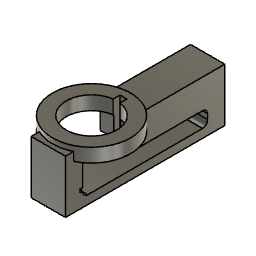
lens-mount (Autodesk Fusion 360 design; units mm, degrees)
Autodesk Fusion 360 part; units mm, degrees
sketch "スケッチ1" plane through (0, 0, 0) normal (0, 0, 1) x (1, 0, 0)
  circle A0 centre (0, 0) radius 14.75
  line L0 (-10, 10.8426) -> (-10, 57.8)
  line L1 (-10, 57.8) -> (10, 57.8)
  line L2 (10, 57.8) -> (10, 10.8426)
  line L3 (-10, -10.8426) -> (-10, -15.2)
  line L4 (10, -15.2) -> (10, -10.8426)
  line L5 (-10, -15.2) -> (10, -15.2)
  line L6 (-10, 57.8) -> (10, 57.8)
  line L7 (10, 57.8) -> (10, 67.8)
  line L8 (10, 67.8) -> (-10, 67.8)
  line L9 (-10, 67.8) -> (-10, 57.8)
  line L10 (-10, -15.2) -> (10, -15.2)
  line L11 (10, -15.2) -> (10, -25.2)
  line L12 (10, -25.2) -> (-10, -25.2)
  line L13 (-10, -25.2) -> (-10, -15.2)
  circle A1 centre (0, 0) radius 22.75
  line L14 (-2, 14.6138) -> (2, 14.6138)
  line L15 (2, 14.6138) -> (2, 18.6138)
  line L16 (2, 18.6138) -> (-2, 18.6138)
  line L17 (-2, 18.6138) -> (-2, 14.6138)
  line L18 (10, 14.9991) -> (-10, 15.0009)
  dimension "d1" = 29.5
  dimension "d2" = 73
  dimension "d3" = 20
  dimension "d4" = 15.2
  dimension "d5" = 10
  dimension "d6" = 8
  dimension "d7" = 4
  dimension "d8" = 4
  dimension "d17" = 15
  constraint coincident A0.centre A1.centre
  constraint coincident A0 L0.start
  constraint vertical L0
  constraint perpendicular L0 L1
  constraint coincident A0 L2.end
  constraint perpendicular L1 L2
  constraint coincident A0 L3.start
  constraint parallel L0 L3
  constraint coincident A0 L4.end
  constraint parallel L0 L4
  constraint perpendicular L3 L5
  constraint equal L0 L2
  constraint equal L3 L4
  constraint equal L1 L5
  constraint horizontal L6
  constraint vertical L7
  constraint horizontal L8
  constraint vertical L9
  constraint horizontal L10
  constraint vertical L11
  constraint horizontal L12
  constraint vertical L13
  constraint equal L7 L11
  constraint coincident L1.end L2.start
  constraint coincident L4.start L5.end
  constraint concentric A0 A1
  constraint horizontal L14
  constraint vertical L15
  constraint horizontal L16
  constraint vertical L17
  constraint coincident A0 L14.start
  constraint coincident A0 L14.end
  constraint coincident L2 L18.start
  constraint coincident L0 L18.end
  measures "d1" diameter of A0
  measures "d2" distance of L1 L5
  measures "d3" distance of L0.end L1.end
  measures "d4" distance of A0.centre L5
  measures "d5" distance of L1.end L7.end
  measures "d6" distance of A0 A1
  measures "d7" distance of L15.end L16.end
  measures "d8" distance of L14.end L15.end
  measures "d17" distance of A0.centre L18
extrude "押し出し1" add sketch "スケッチ1" along normal blind 8 contours A0 L2 L4 L11 A1 | A0 L2 L15 L18 | A0 L3 L4 L5 L10 | L0 L2 A1 L15 L16 L17 L18 | A0 L0 L3 L13 A1 | L5 L10 L11 L13 A1 | A0 L0 L17 L18
extrude "押し出し2" add sketch "スケッチ1" along normal blind 5 contours L0 L1 L2 L6 A1 | L11 L12 L13 A1 | L1 L6 L7 L8 L9
extrude "押し出し3" add sketch "スケッチ1" against normal blind 21 contours L5 L10 L11 L13 A1 | L11 L12 L13 A1 | L1 L6 L7 L8 L9
extrude "押し出し4" add sketch "スケッチ1" against normal blind 12 contours L0 L2 A1 L15 L16 L17 L18 | L0 L1 L2 L6 A1
sketch "スケッチ2" plane through (0, 0, -21) normal (0, 0, -1) x (1, 0, 0)
  line L0 (10, 25.2) -> (-10, 25.2)
  line L1 (-10, 25.2) -> (-10, 15.2)
  line L2 (-10, 15.2) -> (10, 15.2)
  line L3 (10, 15.2) -> (10, 25.2)
  line L4 (10, 25.2) -> (-10, 25.2)
  line L5 (-10, 25.2) -> (-10, -67.8)
  line L6 (-10, -67.8) -> (10, -67.8)
  line L7 (10, -67.8) -> (10, 25.2)
  point P0 (10, -67.8)
  point P1 (-10, -67.8)
  constraint horizontal L4
  constraint vertical L5
  constraint horizontal L6
  constraint vertical L7
  constraint coincident L0.start L3.end
  constraint coincident L6 P0
  constraint coincident L5 P1
extrude "押し出し5" add sketch "スケッチ2" along normal blind 5
sketch "スケッチ3" plane through (10, 0, 0) normal (1, 0, 0) x (0, 1, 0)
  line L0 (67.8, -26) -> (67.8, 5)
  line L1 (67.8, 5) -> (20.4343, 5)
  line L2 (20.4343, 5) -> (20.4343, 0)
  line L3 (20.4343, 0) -> (14.9991, 0)
  line L4 (14.9991, 0) -> (14.9991, -12)
  line L5 (14.9991, -12) -> (57.8, -12)
  line L6 (57.8, -12) -> (57.8, -21)
  line L7 (57.8, -21) -> (-15.2, -21)
  line L8 (-15.2, -21) -> (-15.2, 0)
  line L9 (-15.2, 0) -> (-20.4343, 0)
  line L10 (-20.4343, 0) -> (-20.4343, 5)
  line L11 (-20.4343, 5) -> (-25.2, 5)
  line L12 (-25.2, 5) -> (-25.2, -26)
  line L13 (-25.2, -26) -> (67.8, -26)
  line L14 (-15.2, -17.7) -> (-16.7, -17.7)
  line L15 (-16.7, -17.7) -> (-16.7, -15.9)
  line L16 (-16.7, -15.9) -> (-15.2, -15.9)
  line L17 (-15.2, -15.9) -> (-15.2, -17.7)
  dimension "d20" = 1.5
  dimension "d21" = 1.8
  dimension "d22" = 3.3
  constraint horizontal L14
  constraint vertical L15
  constraint horizontal L16
  constraint vertical L17
  constraint coincident L8 L14.start
  measures "d20" distance of L15.end L16.end
  measures "d21" distance of L14.end L15.end
  measures "d22" distance of L7 L14.start
extrude "押し出し6" cut sketch "スケッチ3" against normal blind 30 contours L8 L14 L15 L16 L17
fillet "フィレット1" radius 3 3 edges at (0, -15.2, -21) (0, 57.8, -12) (0, 57.8, -21)
